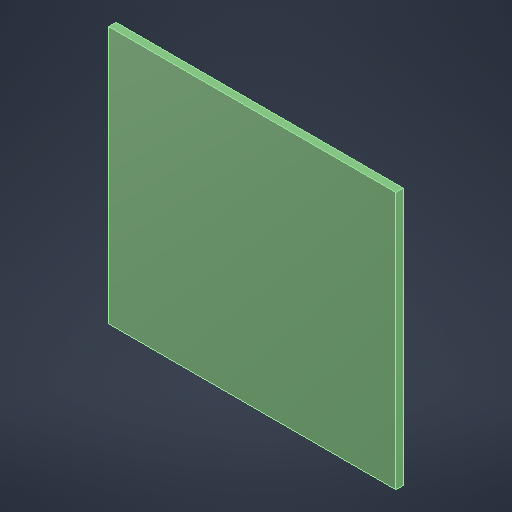
# Autodesk Inventor part: Electronic front
Saved by Autodesk Inventor 2027 (Build 310192060, 192F)
## iProperties
Created: 2026-10-17
Part Number: Electronic front
Material: Générique
Document SubType Name: Modeling
Designer: strei
Density: 1 g/cm^3
Appearance: Lisse - Vert forêt foncé
Author: strei
Autodesk Inventor part; units mm, degrees
ref_plane "YZ Plane" through (0, 0, 0) normal (1, 0, 0) x (0, 1, 0)
ref_plane "XZ Plane" through (0, 0, 0) normal (0, 1, 0) x (-1, 0, 0)
ref_plane "XY Plane" through (0, 0, 0) normal (0, 0, 1) x (1, 0, 0)
sketch "Esquisse1" plane through (0, 0, 0) normal (0, 0, 1) x (1, 0, 0)
  line L0 (-385, 345) -> (385, 345)
  line L1 (385, 345) -> (385, -345)
  line L2 (385, -345) -> (-385, -345)
  line L3 (-385, -345) -> (-385, 345)
  line L4 (-385, 345) -> (385, -345) construction
  line L5 (385, 345) -> (-385, -345) construction
  point P0 (0, 0)
  dimension "d0" = 770
  dimension "d1" = 690
  constraints: 12 end point, 2 midpoint, 2 parallel, 1 horizontal, 1 perpendicular
  measures "d0" distance of L1.end L2.end
  measures "d1" distance of L0.end L1.end
extrude "Extrusion1" add sketch "Esquisse1" along normal blind 20
